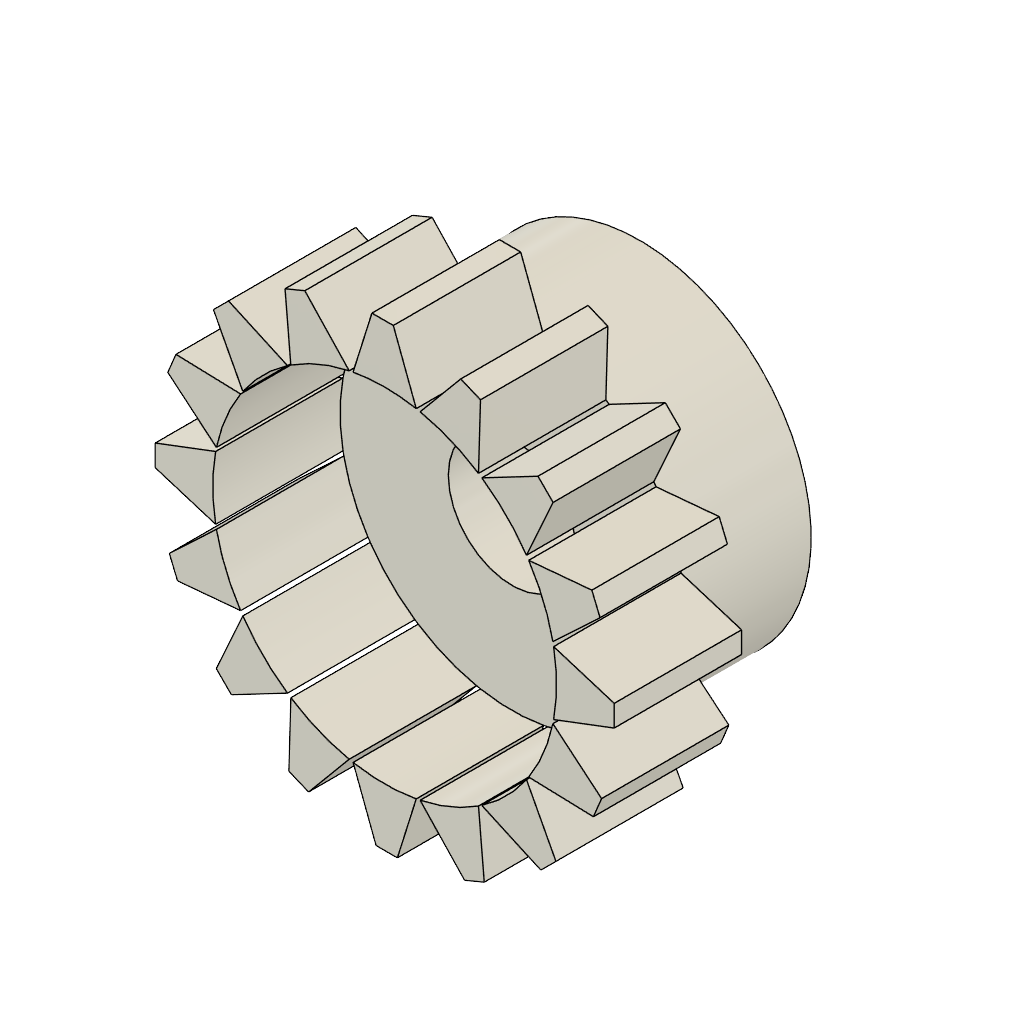
Gripper_Assembly (Autodesk Fusion 360 archive; units mm, degrees)
design "Pinion"
part number: 2026-11-07-16-29-57-265
Autodesk Fusion 360 part; units mm, degrees
sketch "Sketch1" plane through (0, 0, 0) normal (0, 0, 1) x (1, 0, 0)
  circle A0 centre (0, 0) radius 6.75
  dimension "d1" = 13.5
  constraint coincident A0.centre origin
  measures "d1" diameter of A0
extrude "Extrude1" add sketch "Sketch1" along normal blind 5
sketch "Sketch2" plane through (0, 0, 5) normal (0, 0, 1) x (1, 0, 0)
  circle A0 centre (0, 0) radius 6.75
  line L0 (0, 0) -> (0, 9) construction
  line L1 (-1.24, 6.6351) -> (1.24, 6.6351)
  line L2 (1.24, 6.6351) -> (0.3404, 9.0121)
  line L3 (0.3404, 9.0121) -> (-0.4996, 9.0121)
  line L4 (-0.4996, 9.0121) -> (-1.24, 6.6351)
  dimension "d4" = 2.48
  dimension "d5" = 0.84
  dimension "d6" = 9
  dimension "d7" = 6.6351
  constraint coincident A0.centre L0.start
  constraint coincident A0 L1.start
  constraint coincident A0 L1.end
  constraint perpendicular L0 L1
  constraint perpendicular L0 L3
  constraint vertical L0
  measures "d4" distance of L1.start L1.end
  measures "d5" distance of L2.end L3.end
  measures "d6" distance of A0.centre L0.end
  measures "d7" distance of A0.centre L1
extrude "Extrude2" add sketch "Sketch2" along normal blind 5 contours A0 L2 L3 L4
pattern_circular "C-Pattern1" count 16 over 360 about axis through (0, 0, 1.75) along (0, 0, 1) of "Extrude2"
sketch "Sketch3" plane through (0, 0, 5) normal (0, 0, 1) x (1, 0, 0)
  arc A0 (-1.24, 6.6351) -> (-1.3935, 6.6046) centre (0, 0) ccw
  arc A1 (-1.3935, 6.6046) -> (-3.6848, 5.6555) centre (0, 0) ccw
  arc A2 (-3.6848, 5.6555) -> (-3.8149, 5.5686) centre (0, 0) ccw
  arc A3 (-3.8149, 5.5686) -> (-5.5686, 3.8149) centre (0, 0) ccw
  arc A4 (-5.5686, 3.8149) -> (-5.6555, 3.6848) centre (0, 0) ccw
  arc A5 (-5.6555, 3.6848) -> (-6.6046, 1.3935) centre (0, 0) ccw
  arc A6 (-6.6046, 1.3935) -> (-6.6351, 1.24) centre (0, 0) ccw
  arc A7 (-6.6351, 1.24) -> (-6.6351, -1.24) centre (0, 0) ccw
  arc A8 (-6.6351, -1.24) -> (-6.6046, -1.3935) centre (0, 0) ccw
  arc A9 (-6.6046, -1.3935) -> (-5.6555, -3.6848) centre (0, 0) ccw
  arc A10 (-5.6555, -3.6848) -> (-5.5686, -3.8149) centre (0, 0) ccw
  arc A11 (-5.5686, -3.8149) -> (-3.8149, -5.5686) centre (0, 0) ccw
  arc A12 (-3.8149, -5.5686) -> (-3.6848, -5.6555) centre (0, 0) ccw
  arc A13 (-3.6848, -5.6555) -> (-1.3935, -6.6046) centre (0, 0) ccw
  arc A14 (-1.3935, -6.6046) -> (-1.24, -6.6351) centre (0, 0) ccw
  arc A15 (-1.24, -6.6351) -> (1.24, -6.6351) centre (0, 0) ccw
  arc A16 (1.24, -6.6351) -> (1.3935, -6.6046) centre (0, 0) ccw
  arc A17 (1.3935, -6.6046) -> (3.6848, -5.6555) centre (0, 0) ccw
  arc A18 (3.6848, -5.6555) -> (3.8149, -5.5686) centre (0, 0) ccw
  arc A19 (3.8149, -5.5686) -> (5.5686, -3.8149) centre (0, 0) ccw
  arc A20 (5.5686, -3.8149) -> (5.6555, -3.6848) centre (0, 0) ccw
  arc A21 (5.6555, -3.6848) -> (6.6046, -1.3935) centre (0, 0) ccw
  arc A22 (6.6046, -1.3935) -> (6.6351, -1.24) centre (0, 0) ccw
  arc A23 (6.6351, -1.24) -> (6.6351, 1.24) centre (0, 0) ccw
  arc A24 (6.6351, 1.24) -> (6.6046, 1.3935) centre (0, 0) ccw
  arc A25 (6.6046, 1.3935) -> (5.6555, 3.6848) centre (0, 0) ccw
  arc A26 (5.6555, 3.6848) -> (5.5686, 3.8149) centre (0, 0) ccw
  arc A27 (5.5686, 3.8149) -> (3.8149, 5.5686) centre (0, 0) ccw
  arc A28 (3.8149, 5.5686) -> (3.6848, 5.6555) centre (0, 0) ccw
  arc A29 (3.6848, 5.6555) -> (1.3935, 6.6046) centre (0, 0) ccw
  arc A30 (1.3935, 6.6046) -> (1.24, 6.6351) centre (0, 0) ccw
  arc A31 (1.24, 6.6351) -> (-1.24, 6.6351) centre (0, 0) ccw
  circle A32 centre (0, 0) radius 2.5
  dimension "d12" = 5
  constraint concentric A0 A32
  measures "d12" diameter of A32
extrude "Extrude3" cut sketch "Sketch3" against normal through all contours A32

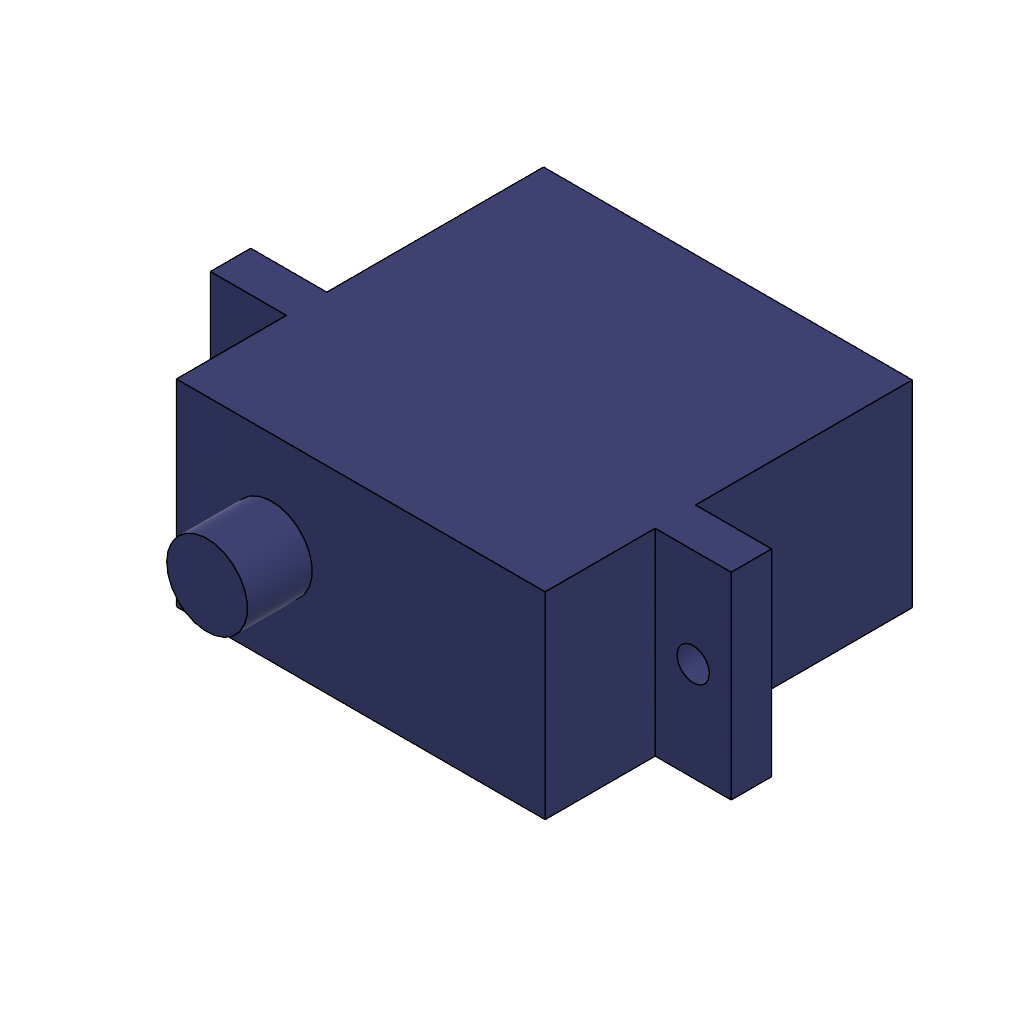
design "Servo_SG90"
part number: 2026-11-06-21-26-01-981
Autodesk Fusion 360 part; units mm, degrees
sketch "Sketch1" plane through (0, 0, 0) normal (0, 0, 1) x (1, 0, 0)
  line L0 (11.4, -6.1) -> (-11.4, -6.1)
  line L1 (-11.4, -6.1) -> (-11.4, 6.1)
  line L2 (-11.4, 6.1) -> (11.4, 6.1)
  line L3 (11.4, 6.1) -> (11.4, -6.1)
  line L4 (11.4, -6.1) -> (-11.4, 6.1) construction
  line L5 (-11.4, -6.1) -> (11.4, 6.1) construction
  dimension "d1" = 22.8
  dimension "d2" = 12.2
  constraint horizontal L0
  constraint perpendicular L0 L1
  constraint parallel L0 L2
  constraint parallel L1 L3
  constraint coincident L4 origin
  constraint coincident L5 origin
  measures "d1" distance of L1.end L2.end
  measures "d2" distance of L0.start L2.end
sketch "Sketch2" plane through (0, 0, 0) normal (0, 0, 1) x (1, 0, 0)
  line L0 (11.4, -6.1) -> (-11.4, -6.1)
  line L1 (-11.4, -6.1) -> (-11.4, 6.1)
  line L2 (-11.4, 6.1) -> (11.4, 6.1)
  line L3 (11.4, 6.1) -> (11.4, -6.1)
  line L4 (11.4, -6.1) -> (-11.4, 6.1) construction
  line L5 (-11.4, -6.1) -> (11.4, 6.1) construction
  dimension "d5" = 22.8
  dimension "d6" = 12.2
  constraint horizontal L0
  constraint perpendicular L0 L1
  constraint parallel L0 L2
  constraint parallel L1 L3
  constraint coincident L4 origin
  constraint coincident L5 origin
  measures "d5" distance of L0.start L0.end
  measures "d6" distance of L0.start L2.end
extrude "Extrude2" add sketch "Sketch2" along normal blind 22.7
sketch "Sketch3" plane through (0, 0, 22.7) normal (0, 0, 1) x (1, 0, 0)
  line L0 (11.4, 6.1) -> (-11.4, 6.1)
  line L1 (-11.4, 6.1) -> (-11.4, -6.1)
  line L2 (-11.4, -6.1) -> (11.4, -6.1)
  line L3 (11.4, -6.1) -> (11.4, 6.1)
  line L4 (16.1, -6.1) -> (-16.1, -6.1)
  line L5 (-16.1, -6.1) -> (-16.1, 6.1)
  line L6 (-16.1, 6.1) -> (16.1, 6.1)
  line L7 (16.1, 6.1) -> (16.1, -6.1)
  line L8 (16.1, -6.1) -> (-16.1, 6.1) construction
  line L9 (-16.1, -6.1) -> (16.1, 6.1) construction
  dimension "d9" = 12.2
  dimension "d10" = 32.2
  constraint horizontal L4
  constraint perpendicular L4 L5
  constraint parallel L4 L6
  constraint parallel L5 L7
  constraint coincident L8 origin
  constraint coincident L9 origin
  measures "d9" distance of L4.end L5.end
  measures "d10" distance of L5.end L6.end
sketch "Sketch4" plane through (0, 0, 38.6) normal (0, 0, 1) x (1, 0, 0)
ref_plane "WorkPlane1" through (0, 0, 13.4) normal (0, 0, 1) x (1, 0, 0)
sketch "Sketch6" plane through (0, 0, 13.4) normal (0, 0, 1) x (1, 0, 0)
  line L0 (16.1, -6.1) -> (-16.1, -6.1)
  line L1 (-16.1, -6.1) -> (-16.1, 6.1)
  line L2 (-16.1, 6.1) -> (16.1, 6.1)
  line L3 (16.1, 6.1) -> (16.1, -6.1)
  line L4 (16.1, -6.1) -> (-16.1, 6.1) construction
  line L5 (-16.1, -6.1) -> (16.1, 6.1) construction
  dimension "d18" = 32.2
  dimension "d19" = 12.2
  constraint horizontal L0
  constraint perpendicular L0 L1
  constraint parallel L0 L2
  constraint parallel L1 L3
  constraint coincident L4 origin
  constraint coincident L5 origin
  measures "d18" distance of L1.end L2.end
  measures "d19" distance of L0.start L2.end
extrude "Extrude4" add sketch "Sketch6" along normal blind 2.5
sketch "Sketch7" plane through (0, 0, 15.9) normal (0, 0, 1) x (1, 0, 0)
  line L0 (-11.4, -6.1) -> (-11.4, 6.1)
  line L1 (-11.4, 6.1) -> (-16.1, 6.1)
  line L2 (-16.1, 6.1) -> (-16.1, -6.1)
  line L3 (-16.1, -6.1) -> (-11.4, -6.1)
  circle A0 centre (-13.75, 0) radius 1
  dimension "d22" = 2
  dimension "d23" = 2.35
  dimension "d24" = 6.1
  measures "d22" diameter of A0
  measures "d23" distance of L2 A0.centre
  measures "d24" distance of L1 A0.centre
sketch "Sketch8" plane through (0, 0, 15.9) normal (0, 0, 1) x (1, 0, 0)
  line L0 (11.4, 6.1) -> (11.4, -6.1)
  line L1 (11.4, -6.1) -> (16.1, -6.1)
  line L2 (16.1, -6.1) -> (16.1, 6.1)
  line L3 (16.1, 6.1) -> (11.4, 6.1)
  circle A0 centre (13.75, 0) radius 1
  dimension "d25" = 2
  dimension "d26" = 2.35
  dimension "d27" = 6.1
  measures "d25" diameter of A0
  measures "d26" distance of L0 A0.centre
  measures "d27" distance of L3 A0.centre
extrude "Extrude5" cut sketch "Sketch7" sketch "Sketch8" against normal blind 10 contours A0 of sketch 2 contours A0
sketch "Sketch9" plane through (0, 0, 22.7) normal (0, 0, 1) x (1, 0, 0)
  line L0 (11.4, 6.1) -> (-11.4, 6.1)
  line L1 (-11.4, 6.1) -> (-11.4, -6.1)
  line L2 (-11.4, -6.1) -> (11.4, -6.1)
  line L3 (11.4, -6.1) -> (11.4, 6.1)
  circle A0 centre (-5.5, 0) radius 2.5
  dimension "d30" = 5
  dimension "d31" = 5.9
  dimension "d32" = 6.1
  measures "d30" diameter of A0
  measures "d31" distance of L1 A0.centre
  measures "d32" distance of L0 A0.centre
extrude "Extrude6" add sketch "Sketch9" along normal blind 4 contours A0

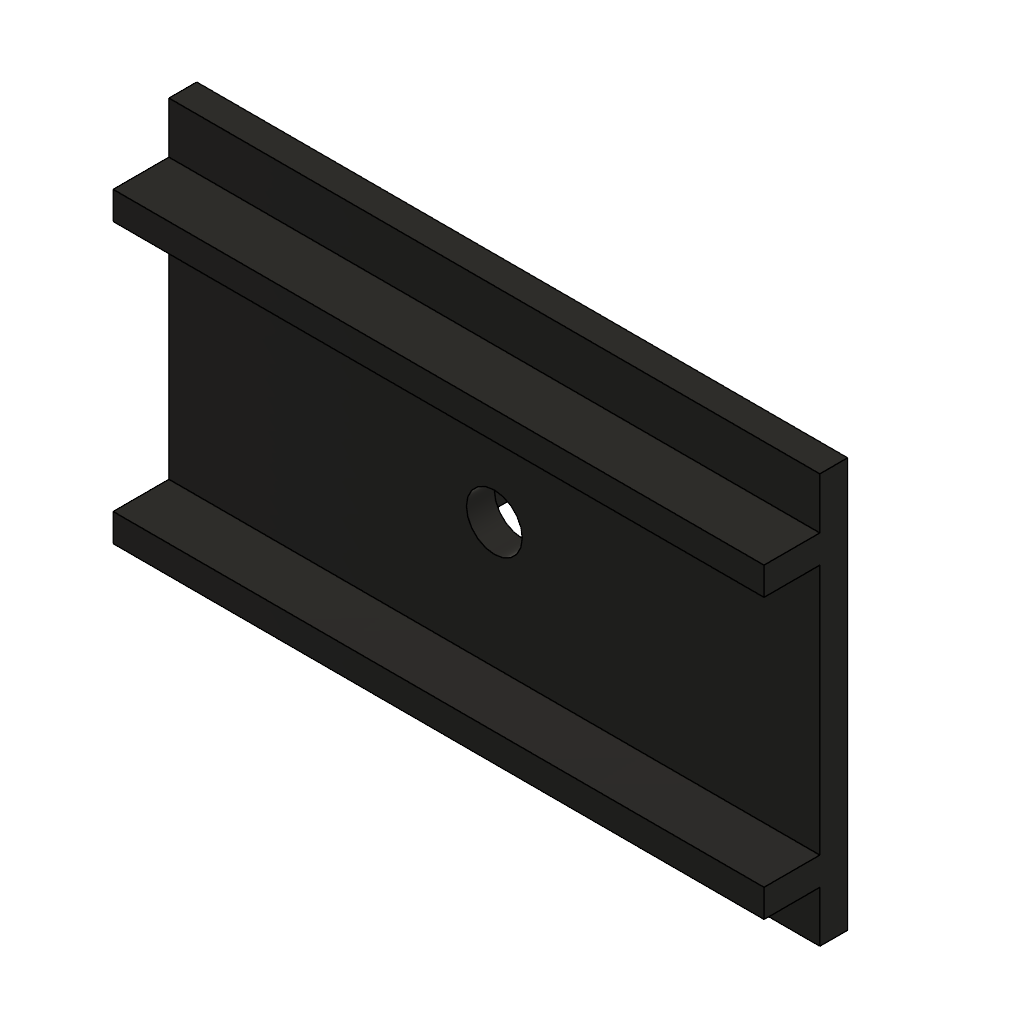
design "Base plate"
part number: 2026-11-06-22-17-30-723
Autodesk Fusion 360 part; units mm, degrees
sketch "Sketch1" plane through (0, 0, 0) normal (0, 0, 1) x (1, 0, 0)
  line L0 (35, -22) -> (-35, -22)
  line L1 (-35, -22) -> (-35, 22)
  line L2 (-35, 22) -> (35, 22)
  line L3 (35, 22) -> (35, -22)
  line L4 (35, -22) -> (-35, 22) construction
  line L5 (-35, -22) -> (35, 22) construction
  circle A0 centre (0, 0) radius 3
  dimension "d1" = 70
  dimension "d2" = 44
  dimension "d3" = 6
  constraint horizontal L0
  constraint perpendicular L0 L1
  constraint parallel L0 L2
  constraint parallel L1 L3
  constraint coincident L4 A0.centre
  constraint coincident L5 A0.centre
  constraint coincident A0.centre origin
  measures "d1" distance of L0.start L0.end
  measures "d2" distance of L0.start L2.end
  measures "d3" diameter of A0
extrude "Extrude1" add sketch "Sketch1" along normal blind 3
sketch "Sketch2" plane through (0, 0, 3) normal (0, 0, 1) x (1, 0, 0)
  circle A0 centre (0, 0) radius 3
  line L0 (35, 22) -> (-35, 22)
  line L1 (-35, 22) -> (-35, -22)
  line L2 (-35, -22) -> (35, -22)
  line L3 (35, -22) -> (35, 22)
  line L4 (-35, 16.5) -> (35, 16.5)
  line L5 (35, 16.5) -> (35, 13.5)
  line L6 (35, 13.5) -> (-35, 13.5)
  line L7 (-35, 13.5) -> (-35, 16.5)
  line L8 (-35, -13.5) -> (35, -13.5)
  line L9 (35, -13.5) -> (35, -16.5)
  line L10 (35, -16.5) -> (-35, -16.5)
  line L11 (-35, -16.5) -> (-35, -13.5)
  dimension "d6" = 3
  dimension "d7" = 3
  dimension "d8" = 5.5
  dimension "d9" = 5.5
  constraint horizontal L4
  constraint vertical L5
  constraint horizontal L6
  constraint vertical L7
  constraint coincident L3 L5.end
  constraint coincident L1 L4.start
  constraint horizontal L8
  constraint vertical L9
  constraint horizontal L10
  constraint vertical L11
  constraint coincident L3 L9.end
  constraint coincident L1 L8.start
  measures "d6" distance of L4.end L5.end
  measures "d7" distance of L8.end L9.end
  measures "d8" distance of L0 L4
  measures "d9" distance of L2 L10
extrude "Extrude2" add sketch "Sketch2" along normal blind 6 contours L1 L3 L4 L5 L6 L7 | L1 L3 L8 L9 L10 L11
sketch "Sketch3" plane through (0, 0, 0) normal (0, 0, -1) x (-1, 0, 0)
  circle A0 centre (0, 0) radius 3
  line L0 (35, 22) -> (-35, 22)
  line L1 (-35, 22) -> (-35, -22)
  line L2 (-35, -22) -> (35, -22)
  line L3 (35, -22) -> (35, 22)
  line L4 (10.6, -5) -> (6.2, -5)
  line L5 (6.2, -5) -> (6.2, 5)
  line L6 (6.2, 5) -> (10.6, 5)
  line L7 (10.6, 5) -> (10.6, -5)
  line L8 (-17.1, -5) -> (-21.5, -5)
  line L9 (-21.5, -5) -> (-21.5, 5)
  line L10 (-21.5, 5) -> (-17.1, 5)
  line L11 (-17.1, 5) -> (-17.1, -5)
  circle A1 centre (8.25, -1.6329) radius 1
  circle A2 centre (-19.25, -2.298) radius 1
  dimension "d12" = 4.4
  dimension "d13" = 10
  dimension "d14" = 24.4
  dimension "d15" = 17
  dimension "d16" = 4.4
  dimension "d17" = 10
  dimension "d18" = 52.1
  dimension "d19" = 17
  dimension "d20" = 2
  dimension "d21" = 2
  dimension "d22" = 8.25
  dimension "d23" = 19.25
  constraint horizontal L4
  constraint vertical L5
  constraint horizontal L6
  constraint vertical L7
  constraint horizontal L8
  constraint vertical L9
  constraint horizontal L10
  constraint vertical L11
  measures "d12" distance of L4.start L4.end
  measures "d13" distance of L4.end L5.end
  measures "d14" distance of L3 L7
  measures "d15" distance of L2 L4
  measures "d16" distance of L8.start L8.end
  measures "d17" distance of L8.end L9.end
  measures "d18" distance of L3 L11
  measures "d19" distance of L2 L8
  measures "d20" diameter of A1
  measures "d21" diameter of A2
  measures "d22" horizontal distance of A0.centre A1.centre
  measures "d23" horizontal distance of A0.centre A2.centre
extrude "Extrude3" add sketch "Sketch3" along normal blind 6.8 contours L4 L5 L6 L7 | L8 L9 L10 L11

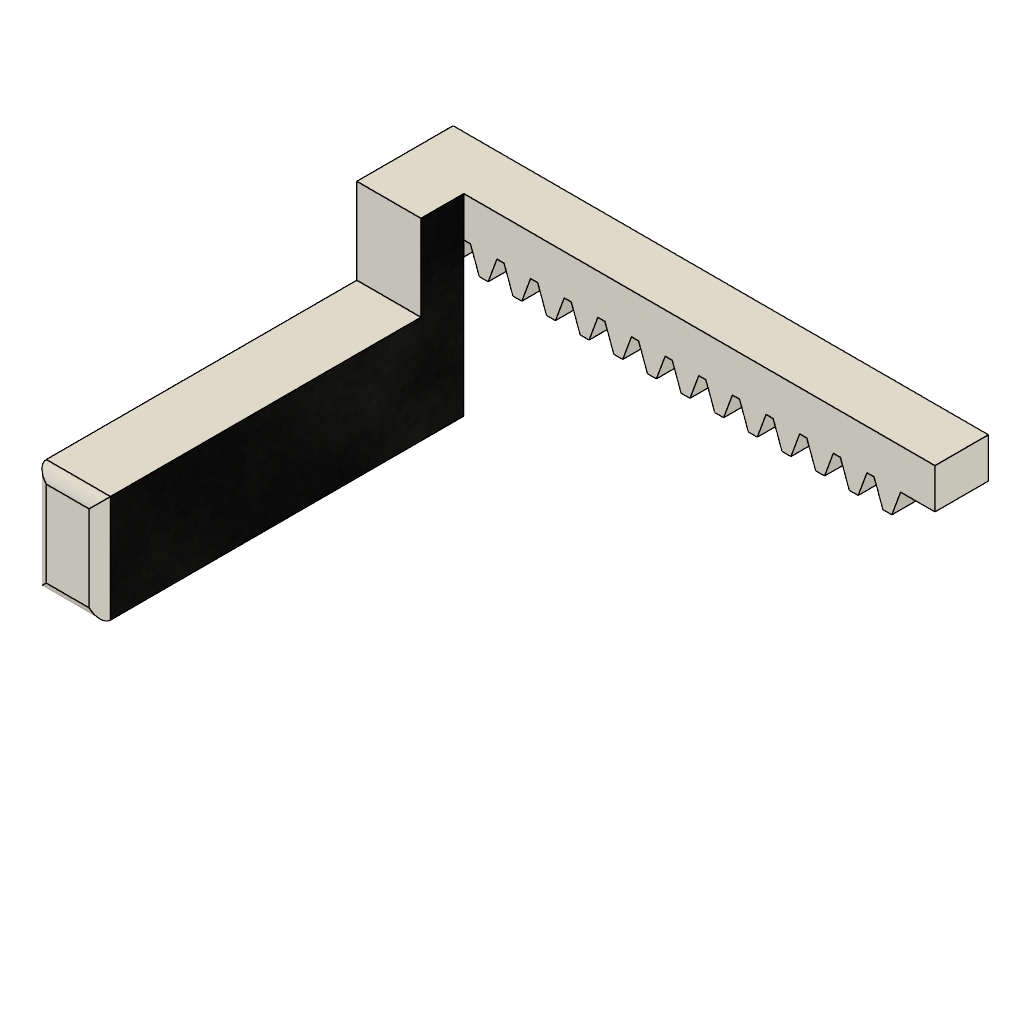
design "Jaw_rack"
part number: 2026-11-07-17-06-24-330
Autodesk Fusion 360 part; units mm, degrees
sketch "Sketch1" plane through (0, 0, 0) normal (0, 0, 1) x (1, 0, 0)
  line L0 (25, -1.875) -> (-25, -1.875)
  line L1 (-25, -1.875) -> (-25, 1.875)
  line L2 (-25, 1.875) -> (25, 1.875)
  line L3 (25, 1.875) -> (25, -1.875)
  line L4 (25, -1.875) -> (-25, 1.875) construction
  line L5 (-25, -1.875) -> (25, 1.875) construction
  dimension "d1" = 50
  dimension "d2" = 3.75
  constraint horizontal L0
  constraint perpendicular L0 L1
  constraint parallel L0 L2
  constraint parallel L1 L3
  constraint coincident L4 origin
  constraint coincident L5 origin
  measures "d1" distance of L1.end L2.end
  measures "d2" distance of L0.end L1.end
extrude "Extrude1" add sketch "Sketch1" along normal blind 5
sketch "Sketch2" plane through (0, 0, 5) normal (0, 0, 1) x (1, 0, 0)
  line L0 (25, 1.875) -> (-25, 1.875)
  line L1 (-25, 1.875) -> (-25, -1.875)
  line L2 (-25, -1.875) -> (25, -1.875)
  line L3 (25, -1.875) -> (25, 1.875)
  line L4 (-24.67, -1.875) -> (-22.19, -1.875)
  line L5 (-23.43, -4.125) -> (-23.01, -4.125)
  line L6 (-23.43, -4.125) -> (-23.85, -4.125)
  line L7 (-22.19, -1.875) -> (-23.01, -4.125)
  line L8 (-23.85, -4.125) -> (-24.67, -1.875)
  dimension "d5" = 0.33
  dimension "d6" = 2.48
  dimension "d8" = 0.42
  dimension "d9" = 0.42
  constraint perpendicular L1 L4
  measures "d5" distance of L1.end L4.start
  measures "d6" distance of L4.start L4.end
  measures "d8" distance of L5.start L5.end
  measures "d9" distance of L5.start L6.end
extrude "Extrude2" add sketch "Sketch2" against normal blind 5 contours L2 L4 L5 L6 L7 L8
pattern_linear "R-Pattern1" count 15 spacing 3.1416 along (1, 0, 0) of "Extrude2"
sketch "Sketch3" plane through (0, 0, 5) normal (0, 0, 1) x (1, 0, 0)
  line L0 (25, 1.875) -> (-25, 1.875)
  line L1 (-25, 1.875) -> (-25, -1.875)
  line L2 (-25, -1.875) -> (-24.67, -1.875)
  line L3 (-24.67, -1.875) -> (-23.85, -4.125)
  line L4 (-23.85, -4.125) -> (-23.01, -4.125)
  line L5 (-23.01, -4.125) -> (-22.19, -1.875)
  line L6 (-22.19, -1.875) -> (-21.5284, -1.875)
  line L7 (-21.5284, -1.875) -> (-20.7084, -4.125)
  line L8 (-20.7084, -4.125) -> (-19.8684, -4.125)
  line L9 (-19.8684, -4.125) -> (-19.0484, -1.875)
  line L10 (-19.0484, -1.875) -> (-18.3868, -1.875)
  line L11 (-18.3868, -1.875) -> (-17.5668, -4.125)
  line L12 (-17.5668, -4.125) -> (-16.7268, -4.125)
  line L13 (-16.7268, -4.125) -> (-15.9068, -1.875)
  line L14 (-15.9068, -1.875) -> (-15.2452, -1.875)
  line L15 (-15.2452, -1.875) -> (-14.4252, -4.125)
  line L16 (-14.4252, -4.125) -> (-13.5852, -4.125)
  line L17 (-13.5852, -4.125) -> (-12.7652, -1.875)
  line L18 (-12.7652, -1.875) -> (-12.1036, -1.875)
  line L19 (-12.1036, -1.875) -> (-11.2836, -4.125)
  line L20 (-11.2836, -4.125) -> (-10.4436, -4.125)
  line L21 (-10.4436, -4.125) -> (-9.6236, -1.875)
  line L22 (-9.6236, -1.875) -> (-8.962, -1.875)
  line L23 (-8.962, -1.875) -> (-8.142, -4.125)
  line L24 (-8.142, -4.125) -> (-7.302, -4.125)
  line L25 (-7.302, -4.125) -> (-6.482, -1.875)
  line L26 (-6.482, -1.875) -> (-5.8204, -1.875)
  line L27 (-5.8204, -1.875) -> (-5.0004, -4.125)
  line L28 (-5.0004, -4.125) -> (-4.1604, -4.125)
  line L29 (-4.1604, -4.125) -> (-3.3404, -1.875)
  line L30 (-3.3404, -1.875) -> (-2.6788, -1.875)
  line L31 (-2.6788, -1.875) -> (-1.8588, -4.125)
  line L32 (-1.8588, -4.125) -> (-1.0188, -4.125)
  line L33 (-1.0188, -4.125) -> (-0.1988, -1.875)
  line L34 (-0.1988, -1.875) -> (0.4628, -1.875)
  line L35 (0.4628, -1.875) -> (1.2828, -4.125)
  line L36 (1.2828, -4.125) -> (2.1228, -4.125)
  line L37 (2.1228, -4.125) -> (2.9428, -1.875)
  line L38 (2.9428, -1.875) -> (3.6044, -1.875)
  line L39 (3.6044, -1.875) -> (4.4244, -4.125)
  line L40 (4.4244, -4.125) -> (5.2644, -4.125)
  line L41 (5.2644, -4.125) -> (6.0844, -1.875)
  line L42 (6.0844, -1.875) -> (6.746, -1.875)
  line L43 (6.746, -1.875) -> (7.566, -4.125)
  line L44 (7.566, -4.125) -> (8.406, -4.125)
  line L45 (8.406, -4.125) -> (9.226, -1.875)
  line L46 (9.226, -1.875) -> (9.8876, -1.875)
  line L47 (9.8876, -1.875) -> (10.7076, -4.125)
  line L48 (10.7076, -4.125) -> (11.5476, -4.125)
  line L49 (11.5476, -4.125) -> (12.3676, -1.875)
  line L50 (12.3676, -1.875) -> (13.0292, -1.875)
  line L51 (13.0292, -1.875) -> (13.8492, -4.125)
  line L52 (13.8492, -4.125) -> (14.6892, -4.125)
  line L53 (14.6892, -4.125) -> (15.5092, -1.875)
  line L54 (15.5092, -1.875) -> (16.1708, -1.875)
  line L55 (16.1708, -1.875) -> (16.9908, -4.125)
  line L56 (16.9908, -4.125) -> (17.8308, -4.125)
  line L57 (17.8308, -4.125) -> (18.6508, -1.875)
  line L58 (18.6508, -1.875) -> (19.3124, -1.875)
  line L59 (19.3124, -1.875) -> (20.1324, -4.125)
  line L60 (20.1324, -4.125) -> (20.9724, -4.125)
  line L61 (20.9724, -4.125) -> (21.7924, -1.875)
  line L62 (21.7924, -1.875) -> (25, -1.875)
  line L63 (25, -1.875) -> (25, 1.875)
  line L64 (-25, 1.875) -> (-19, 1.875)
  line L65 (-19, 1.875) -> (-19, -16.125)
  line L66 (-19, -16.125) -> (-25, -16.125)
  line L67 (-25, -16.125) -> (-25, 1.875)
  dimension "d17" = 18
  dimension "d18" = 6
  constraint horizontal L64
  constraint vertical L65
  constraint horizontal L66
  constraint vertical L67
  constraint coincident L0.end L1.start
extrude "Extrude3" add sketch "Sketch3" along normal blind 4 contours L0 L1 L2 L3 L4 L5 L6 L7 L8 L9 L10 L64 L65 L67 | L2 L3 L4 L5 L6 L7 L8 L9 L10 L65 L66 L67
sketch "Sketch4" plane through (0, 0, 9) normal (0, 0, 1) x (1, 0, 0)
  line L0 (-25, -16.125) -> (-19, -16.125)
  line L1 (-19, -16.125) -> (-19, 1.875)
  line L2 (-19, 1.875) -> (-25, 1.875)
  line L3 (-25, 1.875) -> (-25, -16.125)
  line L4 (-25, -16.125) -> (-19, -16.125)
  line L5 (-19, -16.125) -> (-19, -6.125)
  line L6 (-19, -6.125) -> (-25, -6.125)
  line L7 (-25, -6.125) -> (-25, -16.125)
  dimension "d21" = 10
  dimension "d22" = 6
  constraint horizontal L4
  constraint vertical L5
  constraint horizontal L6
  constraint vertical L7
  constraint coincident L0.start L3.end
  measures "d22" distance of L5.end L6.end
extrude "Extrude4" add sketch "Sketch4" along normal blind 30 contours L0 L1 L3 L4 L5 L6 L7
fillet "Fillet1" radius 1 4 edges at (-22, -6.125, 39) (-19, -11.125, 39) (-22, -16.125, 39) (-25, -11.125, 39)
equation "d8 = ( 0.84 / 2 ) * 1 mm"
